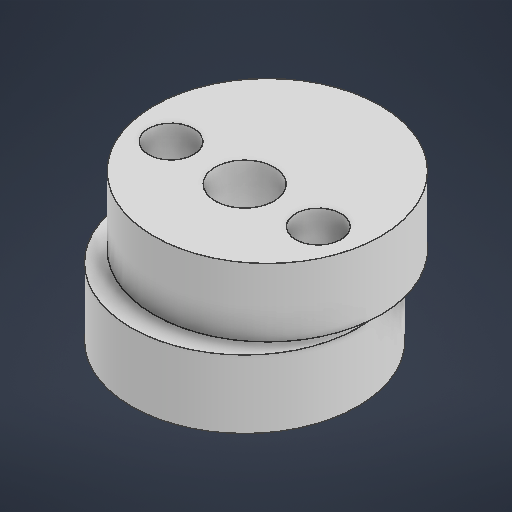
# Autodesk Inventor part: s1
Saved by Autodesk Inventor 2026.2 (Build 302298010, 298A)
## iProperties
Created: 2026-03-31
Part Number: s1
Material: 일반
Document SubType Name: Modeling
Designer: work
Density: 1 g/cm^3
Appearance: 기본값
Author: work
Autodesk Inventor part; units mm, degrees
ref_plane "YZ Plane" through (0, 0, 0) normal (1, 0, 0) x (0, 1, 0)
ref_plane "XZ Plane" through (0, 0, 0) normal (0, 1, 0) x (-1, 0, 0)
ref_plane "XY Plane" through (0, 0, 0) normal (0, 0, 1) x (1, 0, 0)
sketch "스케치1" plane through (0, 0, 0) normal (0, 1, 0) x (-1, 0, 0)
  circle A0 centre (0, 0) radius 2.6
  line L0 (-6.5, 0) -> (6.5, 0) construction
  circle A1 centre (6.5, 0) radius 2
  circle A2 centre (-6.5, 0) radius 2
  circle A3 centre (0, 0) radius 10
  dimension "d0" = 5.2
  dimension "d1" = 13
  dimension "d2" = 4
  dimension "d3" = 4
  dimension "d4" = 20
  constraints: 4 centre point, 4 coincident, 2 end point, 1 horizontal, 1 midpoint
  measures "d0" diameter of A0
  measures "d1" distance of L0.start L0.end
  measures "d2" diameter of A1
  measures "d3" diameter of A2
  measures "d4" diameter of A3
extrude "돌출1" add sketch "스케치1" along normal blind 6
sketch "스케치2" plane through (0, 6, 0) normal (0, 1, 0) x (1, 0, 0)
  line L0 (0, 0) -> (0, 2) construction
  circle A0 centre (0, 2) radius 10
  circle A1 centre (0, 0) radius 10 projected
  circle A2 centre (6.5, 0) radius 2 projected
  circle A3 centre (-6.5, 0) radius 2 projected
  circle A4 centre (0, 0) radius 2.6 projected
  dimension "d7" = 2
  dimension "d8" = 20
  constraints: 2 end point, 1 centre point, 1 coincident, 1 vertical
  measures "d7" distance of L0.start L0.end
  measures "d8" diameter of A0
extrude "돌출2" add sketch "스케치2" along normal blind 6 contours A0 A1 | A1 A0 picked at (1.0573, 10.5578) picked at (-4.5163, 3.734)
sketch "스케치3" plane through (0, 0, 0) normal (0, -1, 0) x (1, 0, 0)
  circle A0 centre (0, 0) radius 10 projected
  circle A1 centre (6.5, 0) radius 2 projected
  circle A2 centre (-6.5, 0) radius 2 projected
  circle A3 centre (0, 0) radius 2.6 projected
  constraints: 2 coincident
hole "구멍1" at (6.5, 0, 0) at (-6.5, 0, 0) direction (0, 1, 0) diameter 4 end through all counterbore diameter 6.2 counterbore depth 3
sketch "스케치4" plane through (0, 0, 0) normal (0, 0, 1) x (1, 0, 0)
  circle A0 centre (0, 3) radius 1.6
  point P0 (0, 0)
  dimension "d18" = 3.2
  dimension "d19" = 3
  constraints: 1 centre point
  measures "d18" diameter of A0
  measures "d19" distance of point (0, 0) A0.centre
extrude "돌출3" cut sketch "스케치4" against normal through all
